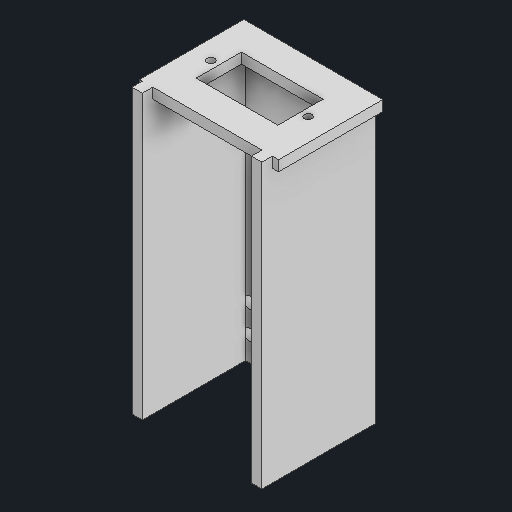
# Autodesk Inventor part: 02_Columna
Saved by Autodesk Inventor 2027.2 (Build 312334000, 334)
## iProperties
Created: 2026-11-14
Part Number: 02_Columna
Material: Genérico
Document SubType Name: Modeling
Designer: alexa
Density: 1 g/cm^3
Appearance: Valor por defecto
Mass: 25.4018 g
Surface Area: 182.572 cm^2
Volume: 25.4018 cm^3
Author: alexa
Autodesk Inventor part; units mm, degrees
ref_plane "Pared_izquierda_perfil_plano" through (0, 0, -14.7) normal (0, 0, 1) x (1, 0, 0)
sketch "Pared_izquierda_perfil" plane through (0, 0, -14.7) normal (0, 0, 1) x (1, 0, 0)
  line L0 (-24.2, 140) -> (-21.2, 140)
  line L1 (-21.2, 140) -> (-21.2, 221.5)
  line L2 (-21.2, 221.5) -> (-24.2, 221.5)
  line L3 (-24.2, 221.5) -> (-24.2, 140)
  constraints: 8 end point, 2 parallel, 1 horizontal, 1 perpendicular
extrude "Pared_izquierda" add sketch "Pared_izquierda_perfil" along normal blind 32.7
ref_plane "Pared_derecha_perfil_plano" through (0, 0, -14.7) normal (0, 0, 1) x (1, 0, 0)
sketch "Pared_derecha_perfil" plane through (0, 0, -14.7) normal (0, 0, 1) x (1, 0, 0)
  line L0 (10.2, 140) -> (13.2, 140)
  line L1 (13.2, 140) -> (13.2, 221.5)
  line L2 (13.2, 221.5) -> (10.2, 221.5)
  line L3 (10.2, 221.5) -> (10.2, 140)
  constraints: 8 end point, 2 parallel, 1 horizontal, 1 perpendicular
extrude "Pared_derecha" add sketch "Pared_derecha_perfil" along normal blind 32.7
ref_plane "Cara_frontal_perfil_plano" through (0, 0, -14.7) normal (0, 0, 1) x (1, 0, 0)
sketch "Cara_frontal_perfil" plane through (0, 0, -14.7) normal (0, 0, 1) x (1, 0, 0)
  line L0 (-21.2, 140) -> (10.2, 140)
  line L1 (10.2, 140) -> (10.2, 221.5)
  line L2 (10.2, 221.5) -> (-21.2, 221.5)
  line L3 (-21.2, 221.5) -> (-21.2, 140)
  constraints: 8 end point, 2 parallel, 1 horizontal, 1 perpendicular
extrude "Cara_frontal" add sketch "Cara_frontal_perfil" along normal blind 3
ref_plane "Placa_servo_yaw_perfil_plano" through (0, 0, -15) normal (0, 0, 1) x (1, 0, 0)
sketch "Placa_servo_yaw_perfil" plane through (0, 0, -15) normal (0, 0, 1) x (1, 0, 0)
  line L0 (-25, 218.5) -> (15, 218.5)
  line L1 (15, 218.5) -> (15, 221.5)
  line L2 (15, 221.5) -> (-25, 221.5)
  line L3 (-25, 221.5) -> (-25, 218.5)
  constraints: 8 end point, 2 parallel, 1 horizontal, 1 perpendicular
extrude "Placa_servo_yaw" add sketch "Placa_servo_yaw_perfil" along normal blind 30
ref_plane "Paso_cuerpo_MG90S_perfil_plano" through (0, 218.4, 0) normal (0, 1, 0) x (-1, 0, 0)
sketch "Paso_cuerpo_MG90S_perfil" plane through (0, 218.4, 0) normal (0, 1, 0) x (-1, 0, 0)
  line L0 (17.2, -6.5) -> (-6.3, -6.5)
  line L1 (-6.3, -6.5) -> (-6.3, 6.5)
  line L2 (-6.3, 6.5) -> (17.2, 6.5)
  line L3 (17.2, 6.5) -> (17.2, -6.5)
  constraints: 8 end point, 2 parallel, 1 horizontal, 1 perpendicular
extrude "Paso_cuerpo_MG90S" cut sketch "Paso_cuerpo_MG90S_perfil" along normal blind 3.2
ref_plane "Fijacion_servo_-19.5_perfil_plano" through (0, 218.3, 0) normal (0, 1, 0) x (-1, 0, 0)
sketch "Fijacion_servo_-19.5_perfil" plane through (0, 218.3, 0) normal (0, 1, 0) x (-1, 0, 0)
  circle A0 centre (19.5, 0) radius 1.1
  constraints: 1 centre point
extrude "Fijacion_servo_-19.5" cut sketch "Fijacion_servo_-19.5_perfil" along normal blind 3.4
ref_plane "Fijacion_servo_8.5_perfil_plano" through (0, 218.3, 0) normal (0, 1, 0) x (-1, 0, 0)
sketch "Fijacion_servo_8.5_perfil" plane through (0, 218.3, 0) normal (0, 1, 0) x (-1, 0, 0)
  circle A0 centre (-8.5, 0) radius 1.1
  constraints: 1 centre point
extrude "Fijacion_servo_8.5" cut sketch "Fijacion_servo_8.5_perfil" along normal blind 3.4
ref_plane "Union_-20_147_perfil_plano" through (0, 0, -14.8) normal (0, 0, 1) x (1, 0, 0)
sketch "Union_-20_147_perfil" plane through (0, 0, -14.8) normal (0, 0, 1) x (1, 0, 0)
  circle A0 centre (-20, 147) radius 1.7
  constraints: 1 centre point
extrude "Union_-20_147" cut sketch "Union_-20_147_perfil" along normal blind 3.2
ref_plane "Union_-20_155_perfil_plano" through (0, 0, -14.8) normal (0, 0, 1) x (1, 0, 0)
sketch "Union_-20_155_perfil" plane through (0, 0, -14.8) normal (0, 0, 1) x (1, 0, 0)
  circle A0 centre (-20, 155) radius 1.7
  constraints: 1 centre point
extrude "Union_-20_155" cut sketch "Union_-20_155_perfil" along normal blind 3.2
ref_plane "Union_9_147_perfil_plano" through (0, 0, -14.8) normal (0, 0, 1) x (1, 0, 0)
sketch "Union_9_147_perfil" plane through (0, 0, -14.8) normal (0, 0, 1) x (1, 0, 0)
  circle A0 centre (9, 147) radius 1.7
  constraints: 1 centre point
extrude "Union_9_147" cut sketch "Union_9_147_perfil" along normal blind 3.2
ref_plane "Union_9_155_perfil_plano" through (0, 0, -14.8) normal (0, 0, 1) x (1, 0, 0)
sketch "Union_9_155_perfil" plane through (0, 0, -14.8) normal (0, 0, 1) x (1, 0, 0)
  circle A0 centre (9, 155) radius 1.7
  constraints: 1 centre point
extrude "Union_9_155" cut sketch "Union_9_155_perfil" along normal blind 3.2
ref_plane "Yaw_apoyo" through (0, 236, 0) normal (0, 1, 0) x (-1, 0, 0)
ref_plane "Servo_yaw_ref_1" through (0, 221.5, 0) normal (1, 0, 0) x (0, 1, 0)
ref_plane "Servo_yaw_ref_2" through (0, 221.5, 0) normal (0, 0, -1) x (1, 0, 0)
ref_plane "Servo_yaw_ref_3" through (0, 221.5, 0) normal (0, 1, 0) x (1, 0, 0)
equation "\"Altura_centro_lente\" = 286"
